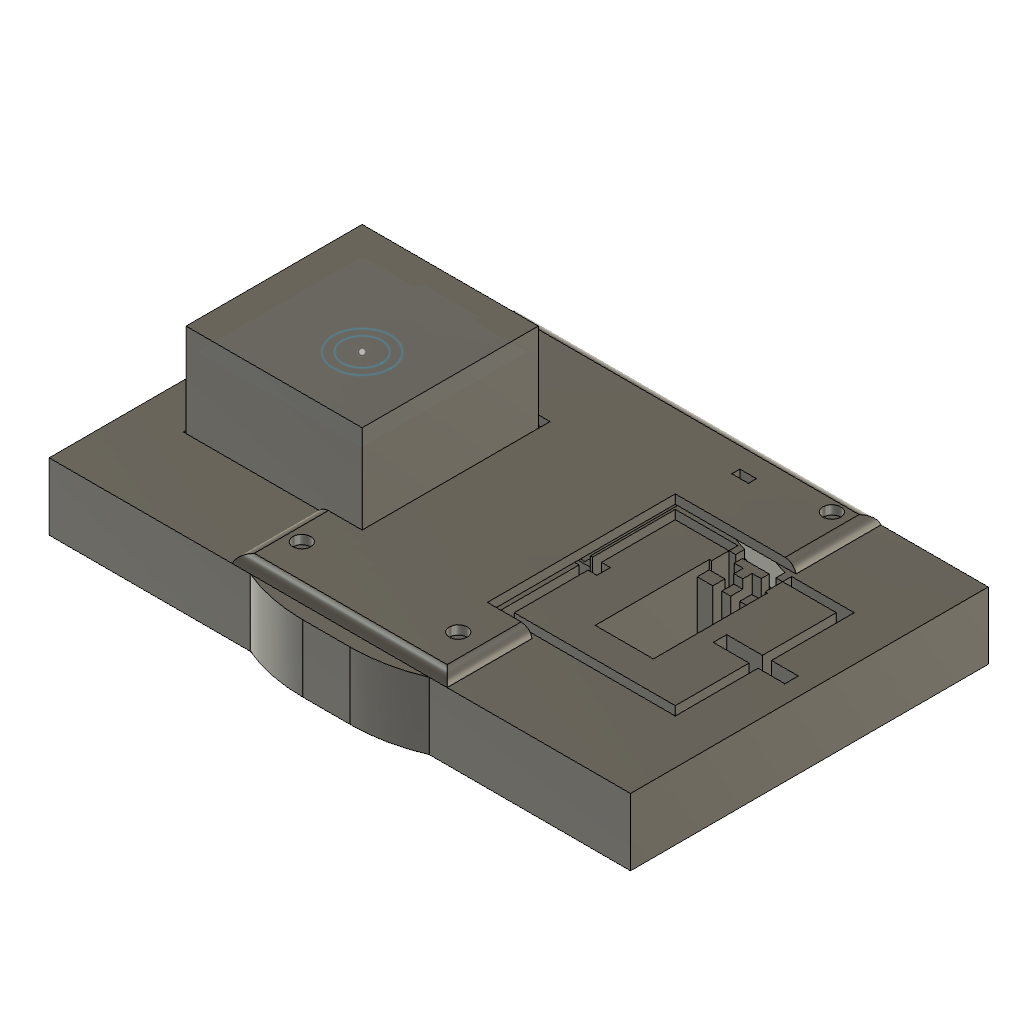
folia (Autodesk Fusion 360 design; units mm, degrees)
part number: 2026-11-17-11-54-46-889
part number: 2026-11-17-12-56-18-282
part number: 2026-11-17-13-28-08-056
part number: 2026-11-17-13-43-19-037
Autodesk Fusion 360 part; units mm, degrees
sketch "Sketch1" plane through (0, 0, 0) normal (0, 0, 1) x (1, 0, 0)
  line L0 (0, 0) -> (130, 0)
  line L1 (130, 0) -> (130, -80)
  line L2 (130, -80) -> (0, -80)
  line L3 (0, -80) -> (0, 0)
  line L4 (10, -20) -> (50, -20)
  line L5 (50, -20) -> (50, -60)
  line L6 (50, -60) -> (10, -60)
  line L7 (10, -60) -> (10, -20)
  line L8 (23.5, -25.9) -> (36.5, -25.9)
  line L9 (36.5, -25.9) -> (36.5, -51.4)
  line L10 (36.5, -51.4) -> (23.5, -51.4)
  line L11 (23.5, -51.4) -> (23.5, -25.9)
  line L12 (23.5, -28.6) -> (36.5, -28.6)
  line L13 (27, -28.6) -> (29, -28.6)
  line L14 (29, -28.6) -> (29, -23.8)
  line L15 (29, -23.8) -> (27, -23.8)
  line L16 (27, -23.8) -> (27, -28.6)
  line L17 (31, -28.6) -> (33, -28.6)
  line L18 (33, -28.6) -> (33, -23.8)
  line L19 (33, -23.8) -> (31, -23.8)
  line L20 (31, -23.8) -> (31, -28.6)
  line L21 (30, -20) -> (30, -60) construction
  line L22 (10, -40) -> (50, -40) construction
  line L23 (65, 0) -> (65, -80) construction
  line L24 (80, -20) -> (80, -60)
  line L25 (99, -28.6) -> (97, -28.6)
  line L26 (120, -40) -> (80, -40) construction
  line L27 (99, -23.8) -> (99, -28.6)
  line L28 (106.5, -51.4) -> (106.5, -25.9)
  line L29 (97, -28.6) -> (97, -23.8)
  line L30 (106.5, -28.6) -> (93.5, -28.6)
  line L31 (101, -23.8) -> (103, -23.8)
  line L32 (93.5, -51.4) -> (106.5, -51.4)
  line L33 (80, -60) -> (120, -60)
  line L34 (93.5, -25.9) -> (93.5, -51.4)
  line L35 (120, -20) -> (80, -20)
  line L36 (101, -28.6) -> (101, -23.8)
  line L37 (106.5, -25.9) -> (93.5, -25.9)
  line L38 (120, -60) -> (120, -20)
  line L39 (103, -28.6) -> (101, -28.6)
  line L40 (100, -20) -> (100, -60) construction
  line L41 (103, -23.8) -> (103, -28.6)
  line L42 (97, -23.8) -> (99, -23.8)
  line L43 (56, -1) -> (74, -1)
  line L44 (74, -1) -> (74, -34.2)
  line L45 (74, -34.2) -> (56, -34.2)
  line L46 (56, -34.2) -> (56, -1)
  line L47 (59, -1) -> (59, 0)
  line L48 (71, -1) -> (71, 0)
  line L49 (51.5, -34.7) -> (76.5, -34.7)
  line L50 (76.5, -34.7) -> (76.5, -79.7)
  line L51 (76.5, -79.7) -> (51.5, -79.7)
  line L52 (51.5, -79.7) -> (51.5, -34.7)
  line L53 (76.5, -34.7) -> (79.5, -34.7)
  line L54 (79.5, -34.7) -> (79.5, -39.7)
  line L55 (79.5, -39.7) -> (76.5, -39.7)
  line L56 (76.5, -39.7) -> (76.5, -34.7)
  line L57 (48, -58) -> (12, -58)
  line L58 (12, -58) -> (12, -22)
  line L59 (12, -22) -> (48, -22)
  line L60 (48, -22) -> (48, -58)
  line L61 (24, -20) -> (24, -22)
  line L62 (36, -20) -> (36, -22)
  line L63 (33, -23.8) -> (33, -22)
  line L64 (36, -22) -> (36, -25.9)
  line L65 (27, -22) -> (27, -23.8)
  line L66 (24, -22) -> (24, -25.9)
  line L67 (25.5, -20) -> (25.5, -22)
  line L68 (34.5, -20) -> (34.5, -22)
  line L69 (95.5, -20) -> (95.5, -22)
  line L70 (94, -22) -> (94, -25.9)
  line L71 (94, -20) -> (94, -22)
  line L72 (106, -20) -> (106, -22)
  line L73 (106, -22) -> (106, -25.9)
  line L74 (104.5, -20) -> (104.5, -22)
  line L75 (103, -22) -> (103, -23.8)
  line L76 (118, -22) -> (82, -22)
  line L77 (82, -22) -> (82, -58)
  line L78 (82, -58) -> (118, -58)
  line L79 (118, -58) -> (118, -22)
  line L80 (97, -23.8) -> (97, -22)
  line L81 (79, -6) -> (87.55, -6)
  line L82 (87.55, -6) -> (87.55, -9.75)
  line L83 (87.55, -9.75) -> (79, -9.75)
  line L84 (79, -9.75) -> (79, -6)
  line L85 (79, -6.2) -> (87.55, -6.2)
  line L86 (79, -9.55) -> (87.55, -9.55)
  line L87 (83.275, -6) -> (83.275, -9.75) construction
  line L88 (80.375, -7.575) -> (81.175, -7.575)
  line L89 (81.175, -7.575) -> (81.175, -8.175)
  line L90 (81.175, -8.175) -> (80.375, -8.175)
  line L91 (80.375, -8.175) -> (80.375, -7.575)
  line L92 (79, -7.875) -> (87.55, -7.875) construction
  line L93 (83.675, -7.575) -> (82.875, -7.575)
  line L94 (82.875, -7.575) -> (82.875, -8.175)
  line L95 (82.875, -8.175) -> (83.675, -8.175)
  line L96 (83.675, -8.175) -> (83.675, -7.575)
  line L97 (83.675, -7.575) -> (82.875, -8.175) construction
  line L98 (82.875, -7.575) -> (83.675, -8.175) construction
  line L99 (85.375, -7.575) -> (86.175, -7.575)
  line L100 (86.175, -7.575) -> (86.175, -8.175)
  line L101 (86.175, -8.175) -> (85.375, -8.175)
  line L102 (85.375, -8.175) -> (85.375, -7.575)
  line L103 (80.375, -7.575) -> (80.375, -4)
  line L104 (81.175, -7.575) -> (81.175, -1)
  line L105 (81.175, -1) -> (74, -1)
  line L106 (80.375, -4) -> (74, -4)
  line L107 (82.875, -8.175) -> (82.875, -11.7165)
  line L108 (82.875, -11.7165) -> (76.5, -15.7)
  line L109 (76.5, -15.7) -> (76.5, -34.7)
  line L110 (79.5, -34.7) -> (79.5, -16.7)
  line L111 (79.5, -16.7) -> (83.675, -14.0912)
  line L112 (83.675, -14.0912) -> (83.675, -8.175)
  line L113 (25.5, -20) -> (56, -10.0899)
  line L114 (74, -10.0899) -> (104.5, -20)
  line L115 (34.5, -20) -> (56, -13.0142)
  line L116 (95.5, -20) -> (74, -13.0142)
  line L117 (51.5, -34.7) -> (51.5, 0)
  line L118 (76.5, -15.7) -> (76.5, 0)
  line L119 (56, -1) -> (51.5, -1)
  line L120 (12, -38.5) -> (20, -38.5)
  line L121 (20, -38.5) -> (20, -41.5)
  line L122 (20, -41.5) -> (12, -41.5)
  line L123 (10, -41.5) -> (3, -41.5)
  line L124 (3, -41.5) -> (3, -38.5)
  line L125 (3, -38.5) -> (10, -38.5)
  line L126 (118, -38.5) -> (110, -38.5)
  line L127 (110, -38.5) -> (110, -41.5)
  line L128 (110, -41.5) -> (118, -41.5)
  line L129 (120, -41.5) -> (126, -41.5)
  line L130 (126, -41.5) -> (126, -38.5)
  line L131 (126, -38.5) -> (120, -38.5)
  line L132 (44, -38.5) -> (51.5, -38.5)
  line L133 (51.5, -38.5) -> (51.5, -41.5)
  line L134 (51.5, -41.5) -> (44, -41.5)
  line L135 (44, -41.5) -> (44, -38.5)
  line L136 (76.5, -38.5) -> (84, -38.5)
  line L137 (84, -38.5) -> (84, -41.5)
  line L138 (84, -41.5) -> (76.5, -41.5)
  line L139 (76.5, -41.5) -> (76.5, -38.5)
  circle A0 centre (81.5, -70) radius 2
  circle A1 centre (46.5, -70) radius 2
  circle A2 centre (30, -5) radius 2
  circle A3 centre (100, -5) radius 2
  point P0 (83.275, -7.875)
  dimension "d1" = 130
  dimension "d2" = 80
  dimension "d3" = 40
  dimension "d4" = 40
  dimension "d9" = 10
  dimension "d10" = 25.5
  dimension "d11" = 13
  dimension "d12" = 2.7
  dimension "d13" = 2
  dimension "d14" = 4.8
  dimension "d15" = 2
  dimension "d16" = 4.8
  dimension "d17" = 6.5
  dimension "d18" = 1
  dimension "d19" = 1
  dimension "d20" = 11.4
  dimension "d21" = 20
  dimension "d22" = 18
  dimension "d23" = 33.2
  dimension "d24" = 9
  dimension "d25" = 1
  dimension "d26" = 6
  dimension "d27" = 6
  dimension "d28" = 25
  dimension "d29" = 45
  dimension "d30" = 3
  dimension "d31" = 5
  dimension "d32" = 13.5
  dimension "d33" = 0.5
  dimension "d36" = 2
  dimension "d37" = 6
  dimension "d38" = 6
  dimension "d39" = 1.5
  dimension "d40" = 1.5
  dimension "d53" = 8.55
  dimension "d54" = 3.75
  dimension "d55" = 0.2
  dimension "d56" = 0.2
  dimension "d57" = 0.8
  dimension "d58" = 0.6
  dimension "d59" = 0.3
  dimension "d60" = 0.8
  dimension "d61" = 0.6
  dimension "d62" = 0.8
  dimension "d63" = 0.6
  dimension "d65" = 2.5
  dimension "d66" = 2.5
  dimension "d67" = 5
  dimension "d68" = 6
  dimension "d69" = 18
  dimension "d70" = 18
  dimension "d71" = 18
  dimension "d72" = 18
  dimension "d73" = 50
  dimension "d74" = 50
  dimension "d75" = 19
  dimension "d76" = 18
  dimension "d78" = 3
  dimension "d79" = 0.3
  dimension "d90" = 7
  dimension "d91" = 8
  dimension "d92" = 1.5
  dimension "d93" = 3
  dimension "d94" = 8
  dimension "d95" = 3
  dimension "d96" = 6
  dimension "d97" = 1.5
  dimension "d98" = 7.5
  dimension "d99" = 3
  dimension "d100" = 1.5
  dimension "d101" = 4
  dimension "d102" = 7.5
  dimension "d103" = 3
  dimension "d104" = 1.5
  dimension "d139" = 4
  dimension "d140" = 10
  dimension "d141" = 5
  dimension "d142" = 4
  dimension "d143" = 5
  dimension "d144" = 10
  dimension "d145" = 4
  dimension "d146" = 26
  dimension "d147" = 5
  dimension "d148" = 4
  dimension "d149" = 5
  dimension "d150" = 26
  constraint horizontal L0
  constraint vertical L1
  constraint horizontal L2
  constraint vertical L3
  constraint horizontal L4
  constraint vertical L5
  constraint horizontal L6
  constraint vertical L7
  constraint coincident L0.start L3.end
  constraint horizontal L8
  constraint vertical L9
  constraint horizontal L10
  constraint vertical L11
  constraint coincident L11 L12.start
  constraint coincident L9 L12.end
  constraint perpendicular L9 L12
  constraint horizontal L13
  constraint vertical L14
  constraint horizontal L15
  constraint vertical L16
  constraint coincident L12 L13.start
  constraint horizontal L17
  constraint vertical L18
  constraint horizontal L19
  constraint vertical L20
  constraint coincident L12 L17.start
  constraint perpendicular L10 L21
  constraint coincident L4 L21.start
  constraint coincident L6 L21.end
  constraint midpoint L4 L21.start
  constraint perpendicular L9 L22
  constraint coincident L5 L22.end
  constraint midpoint L7 L22.start
  constraint midpoint L0 L23.start
  constraint midpoint L2 L23.end
  constraint symmetric L4.start L23 L35.start
  constraint symmetric L4.end L23 L24.start
  constraint symmetric L5.end L23 L24.end
  constraint symmetric L6.end L23 L33.end
  constraint symmetric L8.start L23 L28.end
  constraint symmetric L8.end L23 L34.start
  constraint symmetric L9.end L23 L32.start
  constraint symmetric L10.end L23 L28.start
  constraint symmetric L12.start L23 L30.start
  constraint symmetric L12.end L23 L30.end
  constraint symmetric L13.start L23 L39.start
  constraint symmetric L13.end L23 L36.start
  constraint symmetric L14.end L23 L31.start
  constraint symmetric L15.end L23 L31.end
  constraint symmetric L17.start L23 L25.start
  constraint symmetric L17.end L23 L25.end
  constraint symmetric L18.end L23 L29.end
  constraint symmetric L19.end L23 L27.start
  constraint symmetric L21.start L23 L40.start
  constraint symmetric L21.end L23 L40.end
  constraint symmetric L22.start L23 L26.start
  constraint symmetric L22.end L23 L26.end
  constraint horizontal L43
  constraint vertical L44
  constraint horizontal L45
  constraint vertical L46
  constraint coincident L43 L47.start
  constraint coincident L0 L47.end
  constraint perpendicular L0 L47
  constraint coincident L43 L48.start
  constraint coincident L0 L48.end
  constraint perpendicular L0 L48
  constraint horizontal L49
  constraint vertical L50
  constraint horizontal L51
  constraint vertical L52
  constraint horizontal L53
  constraint vertical L54
  constraint horizontal L55
  constraint vertical L56
  constraint coincident L4 L61.start
  constraint coincident L59 L61.end
  constraint perpendicular L59 L61
  constraint coincident L4 L62.start
  constraint coincident L59 L62.end
  constraint perpendicular L59 L62
  constraint coincident L59 L63.end
  constraint perpendicular L59 L63
  constraint coincident L8 L64.end
  constraint perpendicular L8 L64
  constraint coincident L59 L65.start
  constraint coincident L8 L66.end
  constraint vertical L66
  constraint vertical L65
  constraint coincident L4 L67.start
  constraint coincident L59 L67.end
  constraint perpendicular L59 L67
  constraint coincident L4 L68.start
  constraint coincident L59 L68.end
  constraint perpendicular L59 L68
  constraint symmetric L23 L57.start L77.end
  constraint symmetric L23 L57.end L78.end
  constraint symmetric L23 L58.end L76.start
  constraint symmetric L23 L59.end L76.end
  constraint symmetric L23 L61.start L72.start
  constraint symmetric L23 L61.end L72.end
  constraint symmetric L23 L62.start L71.start
  constraint symmetric L23 L62.end L70.start
  constraint symmetric L23 L63.end L80.end
  constraint symmetric L23 L64.end L70.end
  constraint symmetric L23 L65.start L75.start
  constraint symmetric L23 L66.end L73.end
  constraint symmetric L23 L67.start L74.start
  constraint symmetric L23 L67.end L74.end
  constraint symmetric L23 L68.start L69.start
  constraint symmetric L23 L68.end L69.end
  constraint horizontal L81
  constraint vertical L82
  constraint horizontal L83
  constraint vertical L84
  constraint coincident L84 L85.start
  constraint coincident L82 L85.end
  constraint perpendicular L82 L85
  constraint coincident L84 L86.start
  constraint coincident L82 L86.end
  constraint perpendicular L82 L86
  constraint midpoint L81 L87.start
  constraint midpoint L83 L87.end
  constraint horizontal L88
  constraint vertical L89
  constraint horizontal L90
  constraint vertical L91
  constraint midpoint L84 L92.start
  constraint midpoint L82 L92.end
  constraint horizontal L93
  constraint perpendicular L93 L94
  constraint parallel L93 L95
  constraint parallel L94 L96
  constraint coincident L97 P0
  constraint coincident L98 P0
  constraint midpoint L87 P0
  constraint horizontal L99
  constraint vertical L100
  constraint horizontal L101
  constraint vertical L102
  constraint perpendicular L81 L103
  constraint perpendicular L81 L104
  constraint coincident L44 L106.end
  constraint perpendicular L83 L107
  constraint perpendicular L53 L110
  constraint vertical L112
  constraint vertical L109
  constraint horizontal L105
  constraint coincident L46 L113.end
  constraint coincident L44 L114.start
  constraint coincident L46 L115.end
  constraint coincident L44 L116.end
  constraint horizontal L106
  constraint coincident L0 L117.end
  constraint perpendicular L0 L117
  constraint coincident L0 L118.end
  constraint perpendicular L0 L118
  constraint coincident L117 L119.end
  constraint perpendicular L117 L119
  constraint coincident L58 L120.start
  constraint perpendicular L11 L120
  constraint perpendicular L22 L121
  constraint coincident L58 L122.end
  constraint perpendicular L58 L122
  constraint coincident L7 L123.start
  constraint perpendicular L7 L123
  constraint perpendicular L123 L124
  constraint coincident L7 L125.end
  constraint perpendicular L7 L125
  constraint collinear L120 L125
  constraint collinear L122 L123
  constraint coincident L79 L126.start
  constraint perpendicular L79 L126
  constraint perpendicular L26 L127
  constraint coincident L79 L128.end
  constraint perpendicular L79 L128
  constraint coincident L38 L129.start
  constraint perpendicular L38 L129
  constraint perpendicular L129 L130
  constraint coincident L38 L131.end
  constraint perpendicular L38 L131
  constraint collinear L126 L131
  constraint collinear L128 L129
  constraint horizontal L132
  constraint vertical L133
  constraint horizontal L134
  constraint vertical L135
  constraint horizontal L136
  constraint vertical L137
  constraint horizontal L138
  constraint vertical L139
  constraint coincident L56 L136.start
  measures "d1" distance of L0.start L0.end
  measures "d2" distance of L0.start L2.end
  measures "d3" distance of L4.start L4.end
  measures "d4" distance of L4.start L6.end
  measures "d9" distance of L3 L7
  measures "d10" distance of L8.end L9.end
  measures "d11" distance of L8.start L8.end
  measures "d12" distance of L8 L12
  measures "d13" distance of L13.start L13.end
  measures "d14" distance of L13.start L15.end
  measures "d15" distance of L17.start L17.end
  measures "d16" distance of L17.start L19.end
  measures "d17" distance of L9 L21
  measures "d18" distance of L14 L21
  measures "d19" distance of L20 L21
  measures "d20" distance of L10.end L22
  measures "d21" distance of L0 L4
  measures "d22" distance of L43.start L43.end
  measures "d23" distance of L43.start L45.end
  measures "d24" distance of L23 L44
  measures "d25" distance of L0 L43
  measures "d26" distance of L23 L48
  measures "d27" distance of L23.start L47.end
  measures "d28" distance of L49.start L49.end
  measures "d29" distance of L49.start L51.end
  measures "d30" distance of L49.end L53.end
  measures "d31" distance of L53.end L54.end
  measures "d32" distance of L23 L52
  measures "d33" distance of L45 L49
  measures "d37" distance of L21 L62
  measures "d38" distance of L21 L61
  measures "d39" distance of L62 L68
  measures "d40" distance of L61 L67
  measures "d53" distance of L81.start L81.end
  measures "d54" distance of L81.start L83.end
  measures "d55" distance of L83 L86
  measures "d56" distance of L81 L85
  measures "d57" distance of L88.start L88.end
  measures "d58" distance of L88.end L89.end
  measures "d59" distance of L88 L92
  measures "d60" distance of L94.end L95.end
  measures "d61" distance of L93.end L94.end
  measures "d62" distance of L99.start L99.end
  measures "d63" distance of L99.start L101.end
  measures "d65" distance of L94 L102
  measures "d66" distance of L89 L96
  measures "d67" distance of L44 L84
  measures "d68" distance of L0 L81
  measures "d69" angle of L35 L114
  measures "d70" angle of L35 L116
  measures "d71" angle of L4 L115
  measures "d72" angle of L4 L113
  measures "d73" angle of L108 L116
  measures "d74" angle of L111 L116
  measures "d75" distance of L49.end L108.end
  measures "d76" distance of L53.end L110.end
  measures "d78" distance of L105 L106
  measures "d79" distance of L92 L99.start
  measures "d90" distance of L124.end L125.end
  measures "d91" distance of L120.start L120.end
  measures "d92" distance of L22 L120
  measures "d93" distance of L123.end L124.end
  measures "d94" distance of L126.start L126.end
  measures "d95" distance of L126.end L127.end
  measures "d96" distance of L129.start L129.end
  measures "d97" distance of L26 L126
  measures "d98" distance of L132.start L132.end
  measures "d99" distance of L132.start L134.end
  measures "d100" distance of L22 L132
  measures "d101" distance of L60 L135
  measures "d102" distance of L136.start L136.end
  measures "d103" distance of L136.start L138.end
  measures "d104" distance of L26 L136
  measures "d139" diameter of A0
  measures "d140" distance of L2 A0.centre
  measures "d141" distance of L50 A0.centre
  measures "d142" diameter of A1
  measures "d143" distance of L52 A1.centre
  measures "d144" distance of L2 A1.centre
  measures "d145" diameter of A2
  measures "d146" distance of L46 A2.centre
  measures "d147" distance of L0 A2.centre
  measures "d148" diameter of A3
  measures "d149" distance of L0 A3.centre
  measures "d150" distance of L44 A3.centre
extrude "Extrude1" add sketch "Sketch1" against normal blind 15 contours L0 L1 L2 L3 L4 L5 L6 L7 L24 L33 L35 L38 L50 L51 L52 L81 L82 L83 L104 L105 L112 L113 L114 L117 L118 L123 L124 L125 L129 L130 L131 L134 L138 | L0 L43 L47 L117 L119 | L0 L43 L47 L48 | L46 L113 L117 L119 | L0 L43 L48 L105 L118 | L43 L44 L45 L46 | L4 L113 L115 L117 | L46 L113 L115 L117 | L4 L59 L61 L67 | L4 L59 L67 L68 | L4 L5 L52 L115 L117 L132 | L44 L45 L46 L49 L109 L115 L116 L117 L118 | L44 L105 L106 L118 | L81 L103 L104 L105 L106 L118 | L4 L5 L6 L7 L57 L58 L59 L60 L61 L134 | L4 L59 L62 L68 | L8 L16 L59 L65 L66 | L49 L50 L51 L52 L56 L133 L139 | L44 L106 L114 L118 | L81 L83 L84 L103 L106 L107 L108 L114 L118 | L8 L9 L10 L11 L57 L58 L59 L60 L64 L66 L120 L121 L122 L132 L134 L135 | L4 L5 L59 L60 L62 L132 | L8 L18 L59 L63 L64 | L8 L14 L15 L19 L20 L59 L63 L65 | L50 L53 L54 L56 L136 | L53 L108 L109 L110 L111 L116 | L5 L52 L132 L133 L134 | L81 L85 L103 L104 | L81 L82 L85 L104 | L44 L114 L116 L118 | L108 L114 L116 L118 | L7 L123 L124 L125 | L8 L11 L12 L16 | L8 L14 L15 L16 | L50 L54 L55 L56 L136 L139 | L24 L35 L54 L110 L111 L116 L136 | L108 L116 L118 | L5 L60 L132 L134 | L81 L84 L85 L103 | L85 L88 L103 L104 | L82 L84 L85 L86 L89 L90 L91 L93 L94 L96 L103 L104 L107 L112 | L108 L111 L112 L114 L116 | L83 L107 L108 L112 L114 | L58 L120 L121 L122 | L8 L12 L13 L14 L16 | L8 L9 L12 L18 | L8 L18 L19 L20 | L24 L50 L54 L55 L136 L138 L139 | L60 L132 L134 L135 | L88 L89 L90 L91 | L35 L111 L112 L114 L116 | L9 L10 L11 L12 L13 L17 | L8 L12 L14 L20 | L8 L12 L17 L18 L20 | L24 L77 L136 L138 | L24 L35 L71 L76 L77 L136 | L82 L83 L86 L112 | L83 L86 L107 L112 | L83 L84 L86 L107 | L35 L69 L74 L76 | L35 L72 L74 L76 | L24 L33 L35 L38 L72 L76 L77 L78 L79 L138 | L77 L136 L137 L138 | L28 L32 L34 L37 L70 L73 L76 L77 L78 L79 L126 L127 L128 L136 L137 L138 | L35 L69 L71 L76 | L86 L95 L107 L112 | L37 L41 L73 L75 L76 | L29 L37 L70 L76 L80 | L93 L94 L95 L96 | L27 L31 L36 L37 L42 L75 L76 L80 | L38 L129 L130 L131 | L28 L30 L37 L41 | L31 L36 L37 L41 | L29 L30 L34 L37 | L27 L29 L37 L42 | L30 L36 L37 L39 L41 | L79 L126 L127 L128 | L25 L27 L29 L30 L37 | L25 L28 L30 L32 L34 L39 | L27 L30 L36 L37 | L99 L100 L101 L102 | A0 | A1 | A2 | A3 makes body 1
extrude "Extrude2" cut sketch "Sketch1" against normal blind 13.5 contours L4 L5 L6 L7 L57 L58 L59 L60 L61 L134 | L4 L5 L59 L60 L62 L132 | L5 L60 L132 L134 | L24 L77 L136 L138 | L24 L35 L71 L76 L77 L136 | L24 L33 L35 L38 L72 L76 L77 L78 L79 L138 bodies 1
extrude "Extrude3" cut sketch "Sketch1" against normal blind 14 contours L9 L10 L11 L12 L13 L17 | L25 L28 L30 L32 L34 L39 bodies 1
extrude "Extrude4" cut sketch "Sketch1" against normal blind 2 contours L8 L11 L12 L16 | L8 L9 L12 L18 | L8 L12 L14 L20 | L28 L30 L37 L41 | L29 L30 L34 L37 | L27 L30 L36 L37 bodies 1
extrude "Extrude5" cut sketch "Sketch1" against normal blind 12 contours L4 L59 L67 L68 | L8 L16 L59 L65 L66 | L8 L18 L59 L63 L64 | L8 L14 L15 L16 | L8 L12 L13 L14 L16 | L8 L18 L19 L20 | L8 L12 L17 L18 L20 | L35 L69 L74 L76 | L37 L41 L73 L75 L76 | L29 L37 L70 L76 L80 | L31 L36 L37 L41 | L27 L29 L37 L42 | L30 L36 L37 L39 L41 | L25 L27 L29 L30 L37 bodies 1
extrude "Extrude6" cut sketch "Sketch1" against normal blind 8 contours L0 L43 L47 L48 | L43 L44 L45 L46 bodies 1
extrude "Extrude7" cut sketch "Sketch1" against normal blind 9 contours L49 L50 L51 L52 L56 L133 L139 | L50 L53 L54 L56 L136 | L50 L54 L55 L56 L136 L139 bodies 1
extrude "Extrude8" cut sketch "Sketch1" against normal blind 5.5 contours L82 L84 L85 L86 L89 L90 L91 L93 L94 L96 L103 L104 L107 L112 bodies 1
extrude "Extrude9" cut sketch "Sketch1" against normal blind 6 contours L81 L82 L85 L104 | L81 L84 L85 L103 | L82 L83 L86 L112 | L83 L84 L86 L107 bodies 1
extrude "Extrude10" cut sketch "Sketch1" against normal blind 8.5 contours L81 L85 L103 L104 | L85 L88 L103 L104 | L88 L89 L90 L91 | L83 L86 L107 L112 | L86 L95 L107 L112 | L93 L94 L95 L96 | L99 L100 L101 L102 bodies 1
extrude "Extrude11" cut sketch "Sketch1" against normal blind 8.5 contours L44 L105 L106 L118 | L81 L103 L104 L105 L106 L118 | L53 L108 L109 L110 L111 L116 | L108 L111 L112 L114 L116 | L83 L107 L108 L112 L114 bodies 1
extrude "Extrude12" cut sketch "Sketch1" against normal blind 6 contours L46 L113 L117 L119 | L4 L113 L115 L117 | L46 L113 L115 L117 | L44 L45 L46 L49 L109 L115 L116 L117 L118 | L44 L106 L114 L118 | L44 L114 L116 L118 | L108 L114 L116 L118 | L108 L116 L118 | L35 L111 L112 L114 L116 bodies 1
copy_body "Body->Comp1" bodies 1 removing the originals makes body 2 in component "bottomcase"
extrude "Extrude1'" cut sketch "Sketch1" against normal blind 5 contours L5 L52 L132 L133 L134 | L7 L123 L124 L125 | L58 L120 L121 L122 | L24 L50 L54 L55 L136 L138 L139 | L60 L132 L134 L135 | L77 L136 L137 L138 | L38 L129 L130 L131 | L79 L126 L127 L128 bodies 2 in component "bottomcase"
sketch "Sketch1 (2)" plane through (0, 0, 0) normal (0, 0, 1) x (1, 0, 0) in component "Button"
  line L0 (50, -20) -> (36, -20)
  line L1 (36, -20) -> (36, -22)
  line L2 (36, -22) -> (48, -22)
  line L3 (48, -22) -> (48, -58)
  line L4 (48, -58) -> (12, -58)
  line L5 (12, -58) -> (12, -22)
  line L6 (12, -22) -> (24, -22)
  line L7 (24, -22) -> (24, -20)
  line L8 (24, -20) -> (10, -20)
  line L9 (10, -20) -> (10, -60)
  line L10 (10, -60) -> (50, -60)
  line L11 (50, -60) -> (50, -20)
  line L12 (36.3, -21.7) -> (48.3, -21.7)
  line L13 (48.3, -21.7) -> (48.3, -58.3)
  line L14 (48.3, -58.3) -> (11.7, -58.3)
  line L15 (11.7, -58.3) -> (11.7, -21.7)
  line L16 (11.7, -21.7) -> (23.7, -21.7)
  line L17 (23.7, -21.7) -> (23.7, -20.3)
  line L18 (23.7, -20.3) -> (10.3, -20.3)
  line L19 (10.3, -20.3) -> (10.3, -59.7)
  line L20 (10.3, -59.7) -> (49.7, -59.7)
  line L21 (49.7, -59.7) -> (49.7, -20.3)
  line L22 (49.7, -20.3) -> (36.3, -20.3)
  line L23 (36.3, -20.3) -> (36.3, -21.7)
  dimension "d107" = -0.3
extrude "Extrude1''" add sketch "Sketch1 (2)" against normal blind 9 separate body contours L12 L13 L14 L15 L16 L17 L18 L19 L20 L21 L22 L23 makes body 3 in component "Button"
sketch "Sketch2" plane through (0, 0, -9) normal (0, 0, -1) x (1, 0, 0) in component "Button"
  line L0 (36.3, 21.7) -> (36.3, 20.3)
  line L1 (36.3, 20.3) -> (49.7, 20.3)
  line L2 (49.7, 20.3) -> (49.7, 59.7)
  line L3 (49.7, 59.7) -> (10.3, 59.7)
  line L4 (10.3, 59.7) -> (10.3, 20.3)
  line L5 (10.3, 20.3) -> (23.7, 20.3)
  line L6 (23.7, 20.3) -> (23.7, 21.7)
  line L7 (23.7, 21.7) -> (11.7, 21.7)
  line L8 (11.7, 21.7) -> (11.7, 58.3)
  line L9 (11.7, 58.3) -> (48.3, 58.3)
  line L10 (48.3, 58.3) -> (48.3, 21.7)
  line L11 (48.3, 21.7) -> (36.3, 21.7)
  line L12 (51.5, 41.5) -> (44, 41.5)
  line L13 (20, 41.5) -> (12, 41.5)
  line L14 (10, 41.5) -> (3, 41.5)
  line L15 (3, 38.5) -> (10, 38.5)
  line L16 (12, 38.5) -> (20, 38.5)
  line L17 (44, 38.5) -> (51.5, 38.5)
  line L18 (51.5, 41.5) -> (51.5, 38.5)
  line L19 (44, 41.5) -> (44, 38.5)
  line L20 (20, 41.5) -> (20, 38.5)
  line L21 (12, 41.5) -> (10, 41.5)
  line L22 (12, 38.5) -> (10, 38.5)
  line L23 (3, 41.5) -> (3, 38.5)
  constraint coincident L12.start L18.start
  constraint coincident L17.end L18.end
  constraint coincident L12.end L19.start
  constraint coincident L17.start L19.end
  constraint coincident L13.start L20.start
  constraint coincident L16.end L20.end
  constraint coincident L13.end L21.start
  constraint coincident L14.start L21.end
  constraint coincident L16.start L22.start
  constraint coincident L15.end L22.end
  constraint coincident L14.end L23.start
  constraint coincident L15.start L23.end
ref_plane "WorkPlane1" through (50.6, -40, -2.5) normal (0, 0, -1) x (1, 0, 0) in component "Button"
sketch "Sketch4" plane through (0, 0, -2.5) normal (0, 0, -1) x (-1, 0, 0) in component "Button"
  line L0 (-3, -41.5) -> (-3, -38.5)
  line L1 (-10, -41.5) -> (-3, -41.5)
  line L2 (-12, -41.5) -> (-10, -41.5)
  line L3 (-20, -41.5) -> (-12, -41.5)
  line L4 (-12, -38.5) -> (-20, -38.5)
  line L5 (-12, -38.5) -> (-10, -38.5)
  line L6 (-20, -41.5) -> (-20, -38.5)
  line L7 (-51.5, -41.5) -> (-51.5, -38.5)
  line L8 (-44, -38.5) -> (-51.5, -38.5)
  line L9 (-51.5, -41.5) -> (-44, -41.5)
  line L10 (-44, -41.5) -> (-44, -38.5)
  line L11 (-50.8, -40.8) -> (-50.8, -39.2)
  line L12 (-44.7, -39.2) -> (-50.8, -39.2)
  line L13 (-44.7, -40.8) -> (-44.7, -39.2)
  line L14 (-50.8, -40.8) -> (-44.7, -40.8)
  line L15 (-3, -38.5) -> (-10, -38.5)
  line L16 (-3.7, -39.2) -> (-10, -39.2)
  line L17 (-12, -39.2) -> (-10, -39.2)
  line L18 (-12, -39.2) -> (-19.3, -39.2)
  line L19 (-19.3, -40.8) -> (-19.3, -39.2)
  line L20 (-19.3, -40.8) -> (-12, -40.8)
  line L21 (-12, -40.8) -> (-10, -40.8)
  line L22 (-10, -40.8) -> (-3.7, -40.8)
  line L23 (-3.7, -40.8) -> (-3.7, -39.2)
  dimension "d112" = -0.7
  dimension "d113" = -0.7
extrude "Extrude2'" add 1 faces at (23.9, -59.2333, 0) along direction (0, 0, 1) blind 20.5 on bodies 3 bodies 3 in component "Button"
sketch "Sketch5" plane through (0, 0, 20.5) normal (0, 0, 1) x (-1, 0, 0) in component "Button"
  line L0 (-36.3, 20.3) -> (-36.3, 21.7)
  line L1 (-36.3, 21.7) -> (-48.3, 21.7)
  line L2 (-48.3, 21.7) -> (-48.3, 58.3)
  line L3 (-48.3, 58.3) -> (-11.7, 58.3)
  line L4 (-11.7, 58.3) -> (-11.7, 21.7)
  line L5 (-11.7, 21.7) -> (-23.7, 21.7)
  line L6 (-23.7, 21.7) -> (-23.7, 20.3)
  line L7 (-23.7, 20.3) -> (-10.3, 20.3)
  line L8 (-10.3, 20.3) -> (-10.3, 59.7)
  line L9 (-10.3, 59.7) -> (-49.7, 59.7)
  line L10 (-49.7, 59.7) -> (-49.7, 20.3)
  line L11 (-49.7, 20.3) -> (-36.3, 20.3)
  line L12 (-49.7, 59.7) -> (-10.3, 59.7)
  line L13 (-10.3, 59.7) -> (-10.3, 20.3)
  line L14 (-10.3, 20.3) -> (-49.7, 20.3)
  line L15 (-49.7, 20.3) -> (-49.7, 59.7)
  constraint horizontal L12
  constraint vertical L13
  constraint horizontal L14
  constraint vertical L15
  constraint coincident L7.end L8.start
  constraint coincident L9.end L10.start
extrude "Extrude3'" add sketch "Sketch5" against normal blind 5 contours L0 L1 L2 L3 L4 L5 L6 L14 bodies 3 in component "Button"
sketch "Sketch6" plane through (0, 0, 15.5) normal (0, 0, -1) x (1, 0, 0) in component "Button"
  line L0 (11.7, 21.7) -> (23.7, 21.7)
  line L1 (23.7, 21.7) -> (23.7, 20.3)
  line L2 (23.7, 20.3) -> (36.3, 20.3)
  line L3 (36.3, 20.3) -> (36.3, 21.7)
  line L4 (36.3, 21.7) -> (48.3, 21.7)
  line L5 (48.3, 21.7) -> (48.3, 58.3)
  line L6 (48.3, 58.3) -> (11.7, 58.3)
  line L7 (11.7, 58.3) -> (11.7, 21.7)
  circle A0 centre (30, 40) radius 4.375
  circle A1 centre (30, 40) radius 6.375
  dimension "d118" = 8.75
  dimension "d119" = 2
  measures "d118" diameter of A0
extrude "Extrude4'" cut sketch "Sketch6" against normal blind 4 contours A0 bodies 3 in component "Button"
extrude "Extrude5'" add sketch "Sketch6" along normal blind 2 contours A1 bodies 3 in component "Button"
sketch "Sketch1 (3)" plane through (0, 0, 0) normal (0, 0, 1) x (-1, 0, 0) in component "Shield"
  line L0 (-80, 41.5) -> (-76.5, 41.5)
  line L1 (-76.5, 41.5) -> (-76.5, 79.7)
  line L2 (-76.5, 79.7) -> (-51.5, 79.7)
  line L3 (-51.5, 79.7) -> (-51.5, 41.5)
  line L4 (-51.5, 41.5) -> (-50, 41.5)
  line L5 (-50, 41.5) -> (-50, 60)
  line L6 (-50, 60) -> (-10, 60)
  line L7 (-10, 60) -> (-10, 41.5)
  line L8 (-10, 41.5) -> (-3, 41.5)
  line L9 (-3, 41.5) -> (-3, 38.5)
  line L10 (-3, 38.5) -> (-10, 38.5)
  line L11 (-10, 38.5) -> (-10, 20)
  line L12 (-10, 20) -> (-24, 20)
  line L13 (-24, 20) -> (-24, 22)
  line L14 (-24, 22) -> (-25.5, 22)
  line L15 (-25.5, 22) -> (-25.5, 20)
  line L16 (-25.5, 20) -> (-51.5, 11.5521)
  line L17 (-51.5, 11.5521) -> (-51.5, 1)
  line L18 (-51.5, 1) -> (-59, 1)
  line L19 (-59, 1) -> (-59, 0)
  line L20 (-59, 0) -> (0, 0)
  line L21 (0, 0) -> (0, 80)
  line L22 (0, 80) -> (-130, 80)
  line L23 (-130, 80) -> (-130, 0)
  line L24 (-130, 0) -> (-71, 0)
  line L25 (-71, 0) -> (-71, 1)
  line L26 (-71, 1) -> (-81.175, 1)
  line L27 (-81.175, 1) -> (-81.175, 6)
  line L28 (-81.175, 6) -> (-87.55, 6)
  line L29 (-87.55, 6) -> (-87.55, 9.75)
  line L30 (-87.55, 9.75) -> (-83.675, 9.75)
  line L31 (-83.675, 9.75) -> (-83.675, 13.2335)
  line L32 (-83.675, 13.2335) -> (-104.5, 20)
  line L33 (-104.5, 20) -> (-104.5, 22)
  line L34 (-104.5, 22) -> (-106, 22)
  line L35 (-106, 22) -> (-106, 20)
  line L36 (-106, 20) -> (-120, 20)
  line L37 (-120, 20) -> (-120, 38.5)
  line L38 (-120, 38.5) -> (-126, 38.5)
  line L39 (-126, 38.5) -> (-126, 41.5)
  line L40 (-126, 41.5) -> (-120, 41.5)
  line L41 (-120, 41.5) -> (-120, 60)
  line L42 (-120, 60) -> (-80, 60)
  line L43 (-80, 60) -> (-80, 41.5)
  line L44 (0, 0) -> (-130, 0)
  line L45 (-130, 0) -> (-130, 80)
  line L46 (-130, 80) -> (0, 80)
  line L47 (0, 80) -> (0, 0)
  line L48 (-24, 20) -> (-24, 22)
  line L49 (-106, 20) -> (-106, 22)
  line L50 (-50, 20) -> (-50, 60)
  line L51 (-80, 20) -> (-80, 60)
  line L52 (-79, 6) -> (-87.55, 6)
  line L53 (-87.55, 9.75) -> (-79, 9.75)
  line L54 (-87.55, 6) -> (-87.55, 9.75)
  line L55 (-79, 9.75) -> (-79, 6)
sketch "Sketch2 (2)" plane through (0, 0, 0) normal (0, 0, 1) x (-1, 0, 0) in component "Shield"
  line L0 (-24, 0) -> (-24, 19)
  line L1 (-24, 19) -> (-51, 19)
  line L2 (-51, 19) -> (-51, 61)
  line L3 (-51, 61) -> (-41, 61)
  line L4 (-41, 61) -> (-41, 80)
  line L5 (-41, 80) -> (-89, 80)
  line L6 (-89, 80) -> (-89, 61)
  line L7 (-89, 61) -> (-79, 61)
  line L8 (-79, 61) -> (-79, 19)
  line L9 (-79, 19) -> (-106, 19)
  line L10 (-106, 19) -> (-106, 0)
  line L11 (-106, 0) -> (-24, 0)
  line L12 (-81.425, 6.975) -> (-85.125, 6.975)
  line L13 (-85.125, 6.975) -> (-85.125, 8.775)
  line L14 (-85.125, 8.775) -> (-81.425, 8.775)
  line L15 (-81.425, 8.775) -> (-81.425, 6.975)
  line L16 (-87.55, 6) -> (-87.55, 9.75)
  line L17 (-87.55, 9.75) -> (-79, 9.75)
  circle A0 centre (-100, 5) radius 2
  circle A1 centre (-30, 5) radius 2
  circle A2 centre (-81.5, 70) radius 2
  circle A3 centre (-46.5, 70) radius 2
  point P0 (-130, 0)
  dimension "d124" = 19
  dimension "d125" = 27
  dimension "d126" = 27
  dimension "d127" = 19
  dimension "d128" = 24
  dimension "d129" = 24
  dimension "d130" = 42
  dimension "d131" = 42
  dimension "d132" = 10
  dimension "d133" = 10
  dimension "d134" = 19
  dimension "d135" = 3.7
  dimension "d136" = 1.8
  dimension "d137" = 2.425
  dimension "d138" = 0.975
  constraint vertical L0
  constraint perpendicular L0 L1
  constraint perpendicular L1 L2
  constraint perpendicular L2 L3
  constraint perpendicular L3 L4
  constraint perpendicular L4 L5
  constraint perpendicular L5 L6
  constraint perpendicular L6 L7
  constraint perpendicular L7 L8
  constraint perpendicular L8 L9
  constraint perpendicular L9 L10
  constraint perpendicular L0 L11
  constraint horizontal L12
  constraint vertical L13
  constraint horizontal L14
  constraint vertical L15
  measures "d124" distance of L0.start L0.end
  measures "d125" distance of L0.end L1.end
  measures "d126" distance of L8.end L9.end
  measures "d127" distance of L9.end L10.end
  measures "d128" distance of L10.end P0
  measures "d129" distance of origin L0.start
  measures "d130" distance of L7.end L8.end
  measures "d131" distance of L1.end L2.end
  measures "d132" distance of L2.end L3.end
  measures "d133" distance of L6.end L7.end
  measures "d134" distance of L5.end L6.end
  measures "d135" distance of L12.start L12.end
  measures "d136" distance of L12.start L14.end
  measures "d137" distance of L13 L16
  measures "d138" distance of L14 L17
extrude "Extrude13" add sketch "Sketch2 (2)" along normal blind 2 separate body makes body 4
fillet "Fillet1" radius 2.5 6 edges at (89, -70.5, 2) (65, -80, 2) (41, -70.5, 2) (24, -9.5, 2) (65, 0, 2) (106, -9.5, 2) on bodies 4
sketch "Sketch2 (3)" plane through (0, -80, 0) normal (0, -1, 0) x (1, 0, 0)
  line L0 (130, 0) -> (0, 0)
  line L1 (0, 0) -> (0, -15)
  line L2 (0, -15) -> (130, -15)
  line L3 (130, -15) -> (130, 0)
  line L4 (45, 0) -> (85, 0)
  line L5 (85, 0) -> (85, -15)
  line L6 (85, -15) -> (45, -15)
  line L7 (45, -15) -> (45, 0)
  dimension "d155" = 45
  dimension "d156" = 45
  constraint horizontal L4
  constraint vertical L5
  constraint horizontal L6
  constraint vertical L7
  constraint coincident L2 L5.end
  constraint coincident L0 L4.start
  measures "d155" distance of L3 L5
  measures "d156" distance of L1 L7
extrude "Extrude2''" add sketch "Sketch2 (3)" along normal blind 3 contours L0 L2 L4 L5 L6 L7 bodies 2 in component "bottomcase"
fillet "Fillet1'" radius 37.5 2 edges at (85, -83, -7.5) (45, -83, -7.5) on bodies 2 in component "bottomcase"
copy_body "CutPasteBodies1" bodies 4 removing the originals makes body 5 in component "Shield"
component "Button" placed x (1, 0, 0) y (0, 1, 0) z (0, 0, 1) at (0, 0, 0)
component "Shield" placed x (1, 0, 0) y (0, 1, 0) z (0, 0, 1) at (0, 0, 0)
component "bottomcase" placed x (1, 0, 0) y (0, 1, 0) z (0, 0, 1) at (0, 0, 0)
